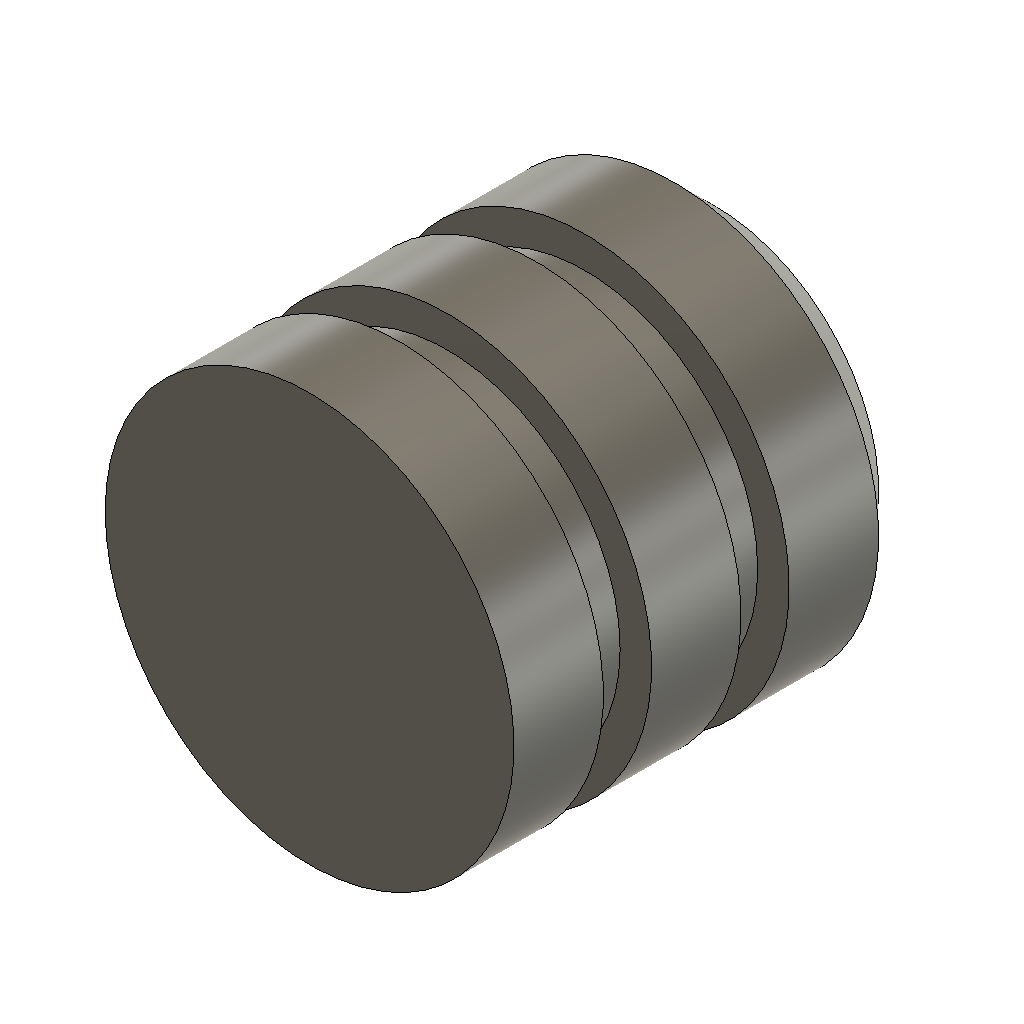
Bouchon de guidage (Autodesk Fusion 360 archive; units mm, degrees)
design "Piston"
part number: 2026-10-20-21-08-35-403
Autodesk Fusion 360 part; units mm, degrees
sketch "Esquisse1" plane through (0, 0, 0) normal (0, 0, 1) x (1, 0, 0)
  circle A0 centre (0, 0) radius 15.25
  dimension "d9" = 30.5
  constraint coincident A0.centre origin
  measures "d9" diameter of A0
extrude "ExtrusionPiston(1)" add sketch "Esquisse1" along normal blind 6.6667
sketch "Esquisse4" plane through (0, 0, 6.6667) normal (0, 0, 1) x (1, 0, 0)
  circle A0 centre (0, 0) radius 15.25
  circle A1 centre (0, 0) radius 12.9
  dimension "d20" = 25.8
  constraint coincident A0.centre A1.centre
  measures "d20" diameter of A1
extrude "ExtrusionGorge(1)" add sketch "Esquisse4" along normal blind 3.6 contours A1
sketch "Esquisse5" plane through (0, 0, 10.2667) normal (0, 0, 1) x (1, 0, 0)
  circle A0 centre (0, 0) radius 12.9
  circle A1 centre (0, 0) radius 15.25
  dimension "d23" = 30.5
  constraint concentric A0 A1
  measures "d23" diameter of A1
extrude "ExtrusionPiston(2) " add sketch "Esquisse5" along normal blind 6.6667 contours A0 | A1
sketch "Esquisse6" plane through (0, 0, 16.9333) normal (0, 0, 1) x (1, 0, 0)
  circle A0 centre (0, 0) radius 15.25
  circle A1 centre (0, 0) radius 12.9
  dimension "d26" = 25.8
  constraint coincident A0.centre A1.centre
  measures "d26" diameter of A1
extrude "ExtrusionGorge(2)" add sketch "Esquisse6" along normal blind 3.6 contours A1
sketch "Esquisse7" plane through (0, 0, 20.5333) normal (0, 0, 1) x (1, 0, 0)
  circle A0 centre (0, 0) radius 12.9
  circle A1 centre (0, 0) radius 15.25
  dimension "d29" = 30.5
  constraint concentric A0 A1
  measures "d29" diameter of A1
extrude "ExtrusionPiston(3)" add sketch "Esquisse7" along normal blind 6.6667 contours A0 | A1
sketch "Esquisse8" plane through (0, 0, 27.2) normal (0, 0, 1) x (1, 0, 0)
  circle A0 centre (0, 0) radius 15.25
  circle A1 centre (0, 0) radius 5.5
  dimension "d32" = 11
  constraint coincident A0.centre A1.centre
  measures "d32" diameter of A1
extrude "Extrusion11" add 1 faces at (1.6584, 3.8611, 0) along direction (0, 0, -1) blind 3
chamfer "Chanfrein1" distance 3 angle 45 1 faces at (1.6584, 3.8611, -3) tangent chain off
equation "DiametrePiston = 31 mm - 0.5 mm" comment "DiamètreSeringue + Jeu"
equation "LongueurPiston = 20 mm"
equation "DiametreGorge = DiametrePiston + 0.5 mm - 6 mm + 0.8 mm" comment "0,5 = diam exacte seringue  6 = Oring  1 = écrasement"
equation "LongueurGorge = ( 3 * 1.2 ) * 1 mm" comment "20% de compression"
equation "EspacementGorges = ( ( LongueurPiston - 5 mm ) / 2 mm ) * 1 mm" comment "5 = espacement 2 = NbGorges"
equation "DiamètreEcrou = 10 mm + 1 mm" comment "3 = Jeu"
equation "DiametreCollerette = 22 mm + 0.3 mm" comment "0,3 = jeu"
equation "ProfondeurEcrou = 15 mm"
equation "d9 = DiametrePiston"
equation "d18 = LongueurPiston / 3"
equation "d20 = DiametreGorge"
equation "d21 = LongueurGorge"
equation "d23 = DiametrePiston"
equation "d24 = LongueurPiston / 3"
equation "d26 = DiametreGorge"
equation "d27 = LongueurGorge"
equation "d29 = DiametrePiston"
equation "d30 = LongueurPiston / 3"
equation "d32 = DiamètreEcrou"
equation "LongueurCollerette = 3.5 mm + 1 mm" comment "1 = jeu"
equation "Chanfrein = 3 mm"
equation "d40 = Chanfrein"
equation "d42 = Chanfrein"
equation "DiametreVis = 3.5 mm"
equation "EpaisseurFermeture = 5 mm"
equation "DistanceVis = 16 mm"
equation "LongueurInsert = 5 mm"
equation "d58 = DiametreVis"
equation "d65 = DistanceVis"
named bodies: "Piston"
